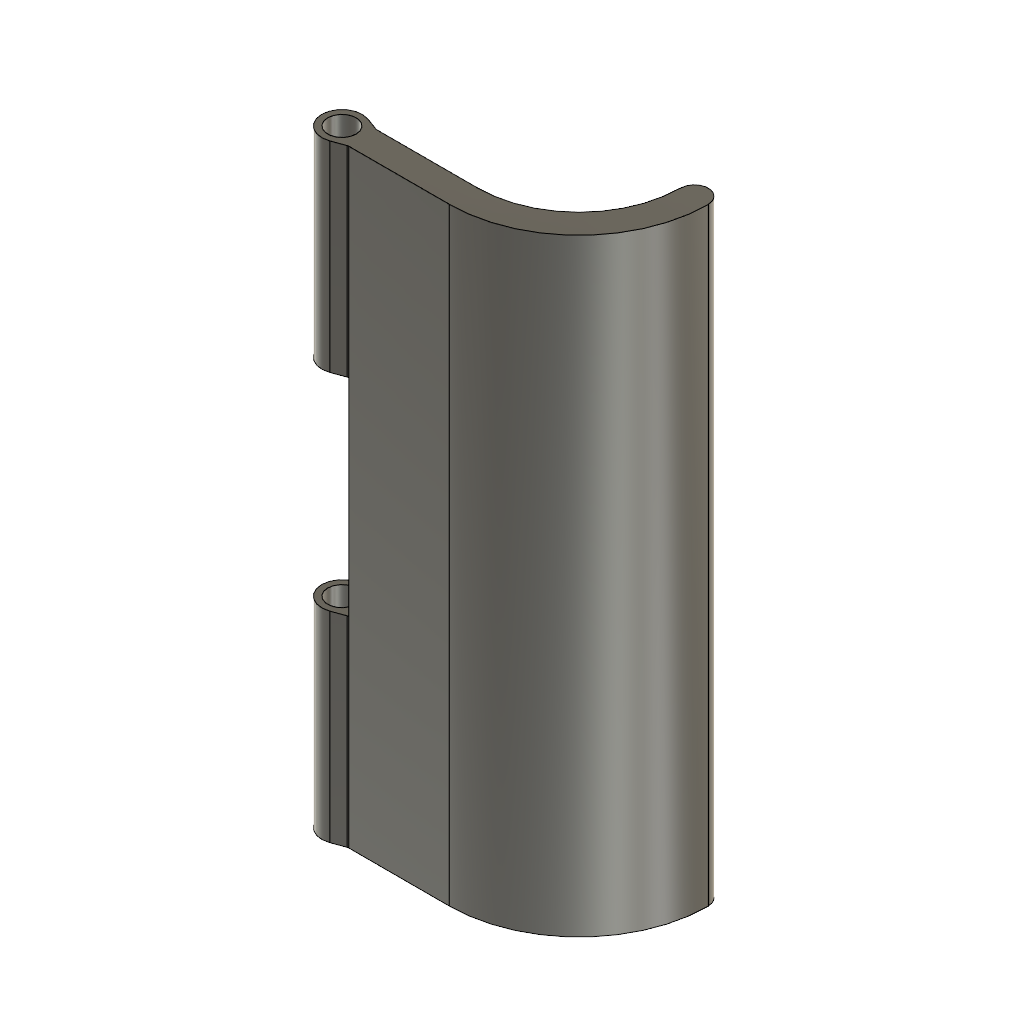
Pintu Gabby (Autodesk Fusion 360 design; units mm, degrees)
Autodesk Fusion 360 part; units mm, degrees
sketch "Sketch1" plane through (0, 0, 0) normal (0, 0, 1) x (1, 0, 0)
  line L0 (-116.8105, 0) -> (116.8105, 0)
  line L1 (25, 125) -> (32, 125)
  line L2 (32, 125) -> (32, 0)
  line L3 (25, 0) -> (25, 125)
  arc A0 (0, -25) -> (25, 0) centre (0, 0) ccw
  line L4 (0, -25) -> (-24.8235, -25)
  line L5 (-24.8235, -32) -> (0, -32)
  line L6 (0, -55.0004) -> (1.362, -68.4592)
  arc A1 (0, -32) -> (32, 0) centre (0, 0) ccw
  line L7 (0, 7.7958) -> (0, -55.0004) construction
  line L8 (-30, -28.5) -> (-20, -28.5)
  line L9 (-25, -25) -> (-25, -32)
  line L10 (-28.2886, -33.198) -> (-25.1658, -32.0604)
  line L11 (-28.2886, -23.802) -> (-25.1658, -24.9396)
  circle A2 centre (-30, -28.5) radius 3.5
  arc A3 (-28.2886, -23.802) -> (-28.2886, -33.198) centre (-30, -28.5) ccw
  arc A4 (-24.8235, -32) -> (-25.1658, -32.0604) centre (-24.8235, -33) ccw
  arc A5 (-25.1658, -24.9396) -> (-24.8235, -25) centre (-24.8235, -24) ccw
  line L12 (-24.8235, -25) -> (-24.8235, -32)
  dimension "d1" = 7
  dimension "d2" = 125
  dimension "d3" = 50
  dimension "d8" = 7
  dimension "d166" = 25
  dimension "d167" = 10
  dimension "d168" = 7
  dimension "d169" = 30
  dimension "d170" = 1
  dimension "d171" = 1
  dimension "d172" = 25.1658
  constraint horizontal L0
  constraint midpoint A0.centre L0
  constraint horizontal L1
  constraint vertical L2
  constraint vertical L3
  constraint coincident L0 L3.start
  constraint coincident A0.centre A1.centre
  constraint horizontal L4
  constraint horizontal L5
  constraint coincident L0 L2.end
  constraint tangent L5 A1
  constraint tangent L2 A1
  constraint perpendicular L5 L7
  constraint coincident A0.centre L7
  constraint parallel L5 L8
  constraint perpendicular L5 L9
  constraint midpoint L8 L9
  constraint coincident L8.start A2.centre
  constraint tangent L11 A3
  constraint tangent L10 A3
  constraint concentric A2 A3
  constraint coincident L5 L9.end
  constraint coincident L9.end L10
  constraint tangent L5 A4
  constraint tangent L10 A4
  constraint coincident L4 L9.start
  constraint coincident L9.start L11
  constraint tangent L4 A5
  constraint tangent L11 A5
  constraint coincident A5 L4.end
  constraint parallel L7 L12
  measures "d1" distance of L1.start L1.end
  measures "d2" distance of L1.start L3.start
  measures "d3" diameter of A0
  measures "d8" distance of L4 L5
  measures "d166" distance of A0.start L9.start
  measures "d167" diameter of A3
  measures "d168" diameter of A2
  measures "d169" distance of L7 L8.start
  measures "d170" radius of A4
  measures "d171" radius of A5
  measures "d172" distance of L7 L10.end
extrude "Extrude1" add sketch "Sketch1" along normal blind 150 contours L0 L1 L2 L3 | L0 A0 L4 L5 A1 L12 makes body 1
sketch "Sketch3" plane through (32, 0, 0) normal (1, 0, 0) x (0, 1, 0)
  line L0 (0, 0) -> (125, 0)
  line L1 (125, 0) -> (125, 150)
  line L2 (125, 150) -> (0, 150)
  line L3 (-110.1294, 75) -> (-66.7455, 75)
  line L4 (-66.7455, 75) -> (170.2287, 75)
  line L5 (62.5, 172.9129) -> (62.5, -172.9129)
  line L6 (125, 0) -> (0, 0)
  line L7 (37.2482, 105) -> (49.9877, 105)
  line L8 (49.9877, 105) -> (49.9877, 55)
  line L9 (49.9877, 55) -> (20, 55)
  line L10 (20, 55) -> (20, 105)
  line L11 (139.0097, 150) -> (139.0097, -7.6637) construction
  line L12 (20.286, 106.6669) -> (25.0007, 119.9999)
  line L13 (25.0007, 119.9999) -> (33.0235, 107.3257)
  arc A0 (20.286, 106.6669) -> (20, 105) centre (25, 105) ccw
  arc A1 (33.0235, 107.3257) -> (37.2482, 105) centre (37.2482, 110) ccw
  line L14 (0, 145) -> (0, 150)
  arc A2 (87.7518, 105) -> (91.9765, 107.3257) centre (87.7518, 110) ccw
  line L15 (99.9993, 119.9999) -> (91.9765, 107.3257)
  arc A3 (105, 105) -> (104.714, 106.6669) centre (100, 105) ccw
  line L16 (105, 55) -> (105, 105)
  line L17 (75.0123, 55) -> (105, 55)
  line L18 (87.7518, 105) -> (75.0123, 105)
  line L19 (104.714, 106.6669) -> (99.9993, 119.9999)
  line L20 (75.0123, 105) -> (75.0123, 55)
  line L21 (0, 150) -> (125, 150)
  line L22 (125, 150) -> (125, 145)
  line L23 (17.5, 52.5) -> (17.5, 105)
  arc A4 (17.9291, 107.5003) -> (17.5, 105) centre (25, 105) ccw
  line L24 (17.9291, 107.5003) -> (24.3598, 125.6865)
  line L25 (24.3598, 125.6865) -> (35.1359, 108.6629)
  arc A5 (35.1359, 108.6629) -> (37.2482, 107.5) centre (37.2482, 110) ccw
  line L26 (37.2482, 107.5) -> (52.4877, 107.5)
  line L27 (52.4877, 107.5) -> (52.4877, 52.5)
  line L28 (52.4877, 52.5) -> (17.5, 52.5)
  line L29 (107.0709, 107.5003) -> (100.6402, 125.6865)
  line L30 (100.6402, 125.6865) -> (89.8641, 108.6629)
  line L31 (87.7518, 107.5) -> (72.5123, 107.5)
  line L32 (72.5123, 107.5) -> (72.5123, 52.5)
  arc A6 (87.7518, 107.5) -> (89.8641, 108.6629) centre (87.7518, 110) ccw
  arc A7 (107.5, 105) -> (107.0709, 107.5003) centre (100, 105) ccw
  line L33 (107.5, 52.5) -> (107.5, 105)
  line L34 (72.5123, 52.5) -> (107.5, 52.5)
  line L35 (0, 150) -> (0, 0)
  point P0 (20, 105.858)
  point P1 (105, 105.858)
  dimension "d31" = 75
  dimension "d32" = 30
  dimension "d34" = 15
  dimension "d36" = 5
  dimension "d40" = 55
  dimension "d42" = 50
  dimension "d43" = 15
  dimension "d66" = -2.5
  constraint perpendicular L2 L5
  constraint midpoint L5 L6
  constraint horizontal L7
  constraint vertical L8
  constraint horizontal L9
  constraint vertical L10
  constraint perpendicular L4 L11
  constraint coincident P0 L10
  constraint coincident P0 L12
  constraint tangent L10 A0
  constraint tangent L12 A0
  constraint tangent L13 A1
  constraint tangent L7 A1
  constraint equal A0 A1
  constraint vertical L14
  constraint coincident L1 L22.end
  constraint coincident L2.end L14.end
  constraint equal L8 L10
  constraint symmetric L5 P0 P1
  constraint symmetric L5 L7.end L18.end
  constraint symmetric L5 L8.end L17.start
  constraint symmetric L5 L9.end L16.start
  constraint symmetric L5 L12.end L15.start
  constraint symmetric L5 L10.end A3.start
  constraint symmetric L5 L12.start A3.end
  constraint symmetric L5 A0 A3
  constraint symmetric L5 L13.end A2.end
  constraint symmetric L5 L7.start A2.start
  constraint symmetric L5 A1 A2
  constraint horizontal L21
  constraint vertical L22
  constraint symmetric L5 L23.start L33.start
  constraint symmetric L5 L23.end A7.start
  constraint symmetric L5 A4.start L29.start
  constraint symmetric L5 A4 A7
  constraint symmetric L5 L24.end L29.end
  constraint symmetric L5 L25.end L30.end
  constraint symmetric L5 A5.end L31.start
  constraint symmetric L5 A5 A6
  constraint symmetric L5 L26.end L31.end
  constraint symmetric L5 L27.end L32.end
  measures "d31" distance of L4 L6
  measures "d32" distance of P0 L7.end
  measures "d34" distance of P0 L12.end
  measures "d36" radius of A0
  measures "d40" distance of L6 L9
  measures "d42" distance of L7.end L8.end
  measures "d43" distance of L12.end L13.end
extrude "Extrude17" add sketch "Sketch1" along normal blind 49.5 contours L10 L11 A3 A4 A5 L12 bodies 1
extrude "Extrude18" add sketch "Sketch1" against normal blind 49.5 from surface at 150 contours L10 L11 A3 A4 A5 L12 bodies 1
extrude "Extrude19" cut sketch "Sketch3" against normal up to surface (7 mm away) contours L4 L7 L8 L10 L12 L13 A0 A1 | L4 L8 L9 L10 | L4 A2 L15 A3 L16 L18 L19 L20 | L4 L16 L17 L20 bodies 1
extrude "Extrude20" add sketch "Sketch3" along normal blind 1.5 contours L4 L7 L8 L10 L12 L13 A0 A1 L23 A4 L24 L25 A5 L26 L27 | L4 L8 L9 L10 L23 L27 L28 | L4 A2 L15 A3 L16 L18 L19 L20 L29 L30 L31 L32 A6 A7 L33 | L4 L16 L17 L20 L32 L33 L34 bodies 1
ref_plane "WorkPlane4" through (28.5, 0, 75) normal (0, 1, 0) x (-1, 0, 0)
split "Split4" by plane through (28.5, 0, 75) normal (0, 1, 0) bodies 1 makes body 2 at (25, 58.3292, 18.3333)
sketch "Sketch9" plane through (0, 0, 150) normal (0, 0, 1) x (-1, 0, 0)
  line L0 (-25, 0) -> (-32, 0)
  line L1 (-32, 0) -> (-32, -125)
  line L2 (-32, -125) -> (-25, -125)
  line L3 (-25, -125) -> (-25, 0)
  arc A0 (-31.95, 0) -> (-25.05, 0) centre (-28.5, 0) ccw
  arc A1 (-32, 0) -> (-25, 0) centre (-28.5, 0) ccw
  line L4 (-32, 0) -> (-31.95, 0) construction
  line L5 (-25.05, 0) -> (-25, 0) construction
  line L6 (-32, 0) -> (-31.95, 0)
  line L7 (-25.05, 0) -> (-25, 0)
  dimension "d249" = 6.9
  constraint midpoint L0 A0.centre
  constraint concentric A0 A1
  constraint coincident L0 A0.end
  constraint coincident L0 A0.start
  constraint coincident L0.end L1.start
  constraint coincident L0.start L3.end
  constraint perpendicular L3 L7
  measures "d249" diameter of A0
extrude "Extrude26" add sketch "Sketch9" against normal up to surface (150 mm away) contours L0 A0 bodies 1
extrude "Extrude27" cut sketch "Sketch9" against normal up to surface (150 mm away) contours L0 A0 bodies 2
sketch "Sketch10" plane through (0, 125, 0) normal (0, 1, 0) x (-1, 0, 0)
  line L0 (-32, 0) -> (-25, 0)
  line L1 (-25, 0) -> (-25, 150)
  line L2 (-25, 150) -> (-32, 150)
  line L3 (-32, 150) -> (-32, 0)
  line L4 (-23, 18) -> (-18, 18)
  line L5 (-18, 18) -> (-18, 6)
  line L6 (-18, 6) -> (-23, 6)
  line L7 (-23, 18) -> (-23, 14)
  line L8 (-23, 14) -> (-25, 14)
  line L9 (-33.297, 12) -> (-15.1367, 12) construction
  line L10 (-23, 6) -> (-25, 6)
  line L11 (-25, 14) -> (-25, 6)
  dimension "d255" = 12
  dimension "d256" = 6
  dimension "d257" = 2
  dimension "d258" = 4
  constraint horizontal L4
  constraint vertical L5
  constraint horizontal L6
  constraint vertical L7
  constraint horizontal L8
  constraint perpendicular L5 L9
  constraint symmetric L4.start L9 L6.end
  constraint coincident L1 L10.end
  constraint perpendicular L1 L10
  constraint perpendicular L10 L11
  measures "d255" distance of L4.end L5.end
  measures "d256" distance of L0 L6
  measures "d257" distance of L7.end L8.end
  measures "d258" distance of L4.start L7.end
extrude "Extrude28" add sketch "Sketch10" against normal blind 125 contours L1 L4 L5 L6 L7 L8 L10 L11 bodies 2
chamfer "Chamfer1" distance 3 angle 45 2 edges at (18, 62.5, 18) (18, 62.5, 6) tangent chain off on bodies 2
sketch "Sketch11" plane through (0, 125, 0) normal (0, 1, 0) x (-1, 0, 0)
  line L0 (-21, 6) -> (-18, 9)
  line L1 (-18, 9) -> (-18, 15)
  line L2 (-18, 15) -> (-21, 18)
  line L3 (-21, 18) -> (-23, 18)
  line L4 (-23, 18) -> (-23, 14)
  line L5 (-23, 14) -> (-25, 14)
  line L6 (-25, 14) -> (-25, 150)
  line L7 (-25, 150) -> (-32, 150)
  line L8 (-32, 150) -> (-32, 0)
  line L9 (-32, 0) -> (-25, 0)
  line L10 (-25, 0) -> (-25, 6)
  line L11 (-25, 6) -> (-21, 6)
  line L12 (-32, 150) -> (-35, 150)
  line L13 (-35, 150) -> (-35, 146)
  line L14 (-35, 146) -> (-33.5, 146)
  line L15 (-32, 147.5) -> (-32, 150)
  line L16 (-32, 147.5) -> (-33.5, 147.5)
  line L17 (-33.5, 147.5) -> (-33.5, 146)
  line L18 (-41.2801, 75) -> (-22.7199, 75)
  line L19 (-35, 0) -> (-35, 4)
  line L20 (-33.5, 2.5) -> (-33.5, 4)
  line L21 (-35, 4) -> (-33.5, 4)
  line L22 (-32, 2.5) -> (-33.5, 2.5)
  line L23 (-32, 0) -> (-35, 0)
  line L24 (-32, 2.5) -> (-32, 0)
  dimension "d262" = 3
  dimension "d263" = 1.5
  dimension "d264" = 1.5
  dimension "d265" = 4
  constraint horizontal L12
  constraint vertical L13
  constraint horizontal L14
  constraint vertical L15
  constraint coincident L7.end L8.start
  constraint horizontal L16
  constraint vertical L17
  constraint coincident L8 L15.start
  constraint perpendicular L8 L18
  constraint midpoint L8 L18
  constraint symmetric L7.end L18 L8.end
  constraint symmetric L12.end L18 L19.start
  constraint symmetric L13.end L18 L19.end
  constraint symmetric L14.end L18 L20.end
  constraint symmetric L15.start L18 L22.start
  constraint symmetric L16.end L18 L20.start
  measures "d262" distance of L7.end L12.end
  measures "d263" distance of L15.start L16.end
  measures "d264" distance of L14.end L16.end
  measures "d265" distance of L12.end L13.end
extrude "Extrude29" add sketch "Sketch11" against normal blind 125 contours L8 L19 L20 L21 L22 L23 L24 | L8 L12 L13 L14 L15 L16 L17 bodies 2
split "Split5" by plane through (25, 0, 0) normal (-1, 0, 0) bodies 2 makes body 3 at (18, 41.6667, 11)
move_body "Move2" bodies 3 to x (1, 0, 0) y (0, 1, 0) z (0, 0, 1) at (-16.5356, 0, 6.961)
ref_plane "WorkPlane5" through (30, 125, 75) normal (0, 1, 0) x (-1, 0, 0)
sketch "Sketch13" plane through (0, 125, 0) normal (0, 1, 0) x (1, 0, 0)
  line L0 (32, -2.5) -> (32, -52.5)
  line L1 (32, -125.6865) -> (32, -147.5)
  line L2 (33.5, -107.5003) -> (33.5, -105)
  line L3 (33.5, -105) -> (33.5, -52.5)
  line L4 (33.5, -125.6865) -> (33.5, -107.5003)
  line L5 (32, -52.5) -> (33.5, -52.5)
  line L6 (32, -125.6865) -> (33.5, -125.6865)
  line L7 (25.05, -150) -> (31.95, -150)
  line L8 (31.95, -150) -> (35, -150)
  line L9 (25, -150) -> (25.05, -150)
  line L10 (31.95, 0) -> (35, 0)
  line L11 (35, 0) -> (35, -4)
  line L12 (35, -4) -> (33.5, -4)
  line L13 (33.5, -4) -> (33.5, -2.5)
  line L14 (33.5, -2.5) -> (32, -2.5)
  line L15 (32, -147.5) -> (33.5, -147.5)
  line L16 (33.5, -147.5) -> (33.5, -146)
  line L17 (33.5, -146) -> (35, -146)
  line L18 (35, -146) -> (35, -150)
  line L19 (25, 0) -> (25, -150)
  line L20 (25.05, 0) -> (25, 0)
  line L21 (31.95, 0) -> (25.05, 0)
  line L22 (42.069, -150) -> (15.2114, -150)
  line L23 (32.25, -144.25) -> (36.75, -144.25)
  line L24 (36.75, -144.25) -> (36.75, -150)
  line L25 (36.75, -155.75) -> (36.75, -150)
  line L26 (35.25, -150) -> (35.25, -145.75)
  line L27 (35.25, -145.75) -> (33.25, -145.75)
  line L28 (33.25, -145.75) -> (33.25, -147.3)
  line L29 (33.25, -147.3) -> (32.25, -147.3)
  line L30 (32.25, -147.3) -> (32.25, -144.25)
  line L31 (36.75, -155.75) -> (36.75, -150)
  line L32 (35.25, -150) -> (35.25, -154.25)
  line L33 (35.25, -154.25) -> (33.25, -154.25)
  line L34 (33.25, -152.7) -> (32.25, -152.7)
  line L35 (33.25, -154.25) -> (33.25, -152.7)
  line L36 (32.25, -152.7) -> (32.25, -155.75)
  line L37 (32.25, -155.75) -> (36.75, -155.75)
  dimension "d270" = 0.25
  dimension "d271" = 0.25
  dimension "d272" = 1
  dimension "d273" = 1.5
  dimension "d274" = 1.5
  dimension "d275" = 0.25
  dimension "d276" = 0.2
  dimension "d277" = 5.75
  constraint perpendicular L18 L22
  constraint horizontal L23
  constraint vertical L24
  constraint coincident L22 L24.end
  constraint symmetric L22 L24.end L25.end
  constraint symmetric L22 L23.end L25.start
  constraint coincident L22 L26.start
  constraint perpendicular L22 L26
  constraint perpendicular L18 L27
  constraint perpendicular L27 L28
  constraint perpendicular L28 L29
  constraint perpendicular L23 L30
  constraint symmetric L22 L26.start L32.start
  constraint symmetric L22 L26.end L32.end
  constraint symmetric L22 L27.end L33.end
  constraint symmetric L22 L28.end L34.start
  constraint symmetric L22 L29.end L34.end
  constraint symmetric L22 L23.start L36.end
  measures "d270" distance of L18 L26
  measures "d271" distance of L16 L28
  measures "d272" distance of L28 L30
  measures "d273" distance of L24 L26
  measures "d274" distance of L23 L27
  measures "d275" distance of L17 L27
  measures "d276" distance of L15 L29
  measures "d277" distance of L24.end L23.end
extrude "Extrude30" add sketch "Sketch13" against normal blind 125 separate body contours L22 L25 L31 L32 L33 L34 L35 L36 L37 | L22 L23 L24 L26 L27 L28 L29 L30 makes body 4
fillet "Fillet2" radius 1.5 4 edges at (36.75, 62.5, 155.75) (36.75, 62.5, 144.25) (32.25, 62.5, 155.75) (32.25, 62.5, 144.25) on bodies 4
hidden bodies 2 3 4
equation "d277 = 4 mm + 0.25 mm + 1.5 mm"
named bodies: "hinge body L1", "window", "latch window (1)", "frontlatch"
